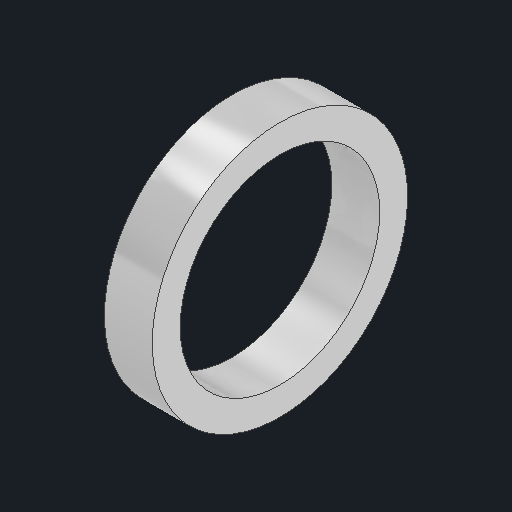
# Autodesk Inventor part: ra_setting_circle
Saved by Autodesk Inventor 2027.1 (Build 311270010, 270A)
## iProperties
Created: 2026-11-03
Part Number: ra_setting_circle
Material: Generic
Description: RA setting circle (hours)
Document SubType Name: Modeling
Designer: Claude (from photos)
Density: 1 g/cm^3
Appearance: Aluminum - Polished
Author: alexg
Autodesk Inventor part; units mm, degrees
ref_plane "XZ Plane" through (0, 0, 0) normal (0, 1, 0) x (-1, 0, 0)
ref_plane "XY Plane" through (0, 0, 0) normal (0, 0, 1) x (1, 0, 0)
ref_plane "Work Plane1" through (-6, 0, 0) normal (1, 0, 0) x (0, 1, 0)
sketch "RA setting circle sketch" plane through (-6, 0, 0) normal (1, 0, 0) x (0, 1, 0)
  circle A0 centre (0, 0) radius 32
  circle A1 centre (0, 0) radius 25
  constraints: 2 centre point
extrude "RA setting circle" add sketch "RA setting circle sketch" along normal blind 12
body "Solid1"
